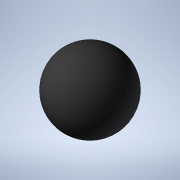
# Autodesk Inventor part: 101013DH-16-B1_ball
Saved by Autodesk Inventor 2021 (Build 250183000, 183)
## iProperties
Created: 2025-04-11
Part Number: 101013DH-16-B1_ball
Material: Generic
Catalog Web Link: www.cadenas.de
Description: DH-A,B,H ball-D-Series bearings
Vendor: TOKBEARING
Document SubType Name: Modeling
Designer: psAdmin
Manufacturer: TOKBEARING
Mass: 11800 g
Surface Area: 0.282743 cm^2
Volume: 0.0141372 cm^3
Density: 1 g/cm^3
Appearance: PSOLRGB-175-175-175
Category: PARTsolutions
Company: TOKBEARING
Title: 101013DH-16-B1_ball
Author: Cadenas PARTsolutions
Comments: D-Series bearings
PSOL_IDENT_0: {$CADENAS_DATA/23d-libs/tok_bearing/d_series_bearings/dh_abh/dh_abh_ball.prj},187 {VTYP=3D},{NB=1010
PSOL_IDENT_1: 13DH-16-B1_ball},{LINA=101013DH-16-B1_ball},{NN=DH-A,B,H ball},{DATE=24.03.2025 06:05:04},{GEOMDATE=
PSOL_IDENT_2: 06.12.2012 07:08:00},{VERSION=},{LINEID=2630},{WBVAR=},{WBNUMERIC=}  {NB=101013DH-16-B1_ball},{LINA=
PSOL_IDENT_3: 101013DH-16-B1_ball},{KT=DUMMY},{IDNR=},{CODE=101013},{PN=DH-16-B1},{D=19},{D1=16.0},{SD=-},{SDX=0.0
PSOL_IDENT_4: 00},{SD1=-},{SD1X=0.000},{W=6},{C=1},{CX=1.000},{L=8},{LX=8.000},{D2XT=-},{D2=0.000},{T=0.000},{G=2.
PSOL_IDENT_5: 1},{TYPE=2},{QTY=2.000},{GW=11.8},{NDM=6.000},{BD=3},{OP=39.878},{N=6},{R=6.35},{GP=2.82}
NB: 101013DH-16-B1_ball
NN: DH-A,B,H ball
NT: D-Series bearings
NBSYN: $CODE.$PN._ball
LINA: 101013DH-16-B1_ball
CATALOG: TOK, Inc
CODE: 101013
PN: DH-16-B1
D: 19
D1: 16
SD: -
SD1: -
W: 6
C: 1
L: 8
D2XT: -
G: 2.1
TYPE: 2
QTY: 2.000
GW: 11.8
SUPPLIER: TOKBEARING
ARTICLENO: 101013DH-16-B1_ball
BOMINFO: 101013DH-16-B1_ball
CREATOR: CADENAS GmbH
Autodesk Inventor part; units mm, degrees
sketch "Sketch_1" plane through (0, 0, 0) normal (0, 0, 1) x (1, 0, 0)
  line L0 (0, 1.5) -> (0, -1.5)
  arc A0 (0, 1.5) -> (0, -1.5) centre (0, 0) ccw
  line L1 (0, 1.5) -> (0, -1.5)
  constraints: 4 end point, 2 point on circle, 1 centre point
revolve "Revolution1" add sketch "Sketch_1" angle 360 about axis through (0, 1.5, 0) along (0, 1, 0)
ref_plane "Ball_Cage_XY" through (0, 0, 0) normal (1, 0, 0) x (0, 0, -1)
ref_plane "Ball_Cage_YZ" through (0, 0, 0) normal (0, 0, -1) x (0, 1, 0)
ref_plane "Ball_Cage_ZX" through (0, 0, 0) normal (0, 1, 0) x (1, 0, 0)
body "Solid1"
